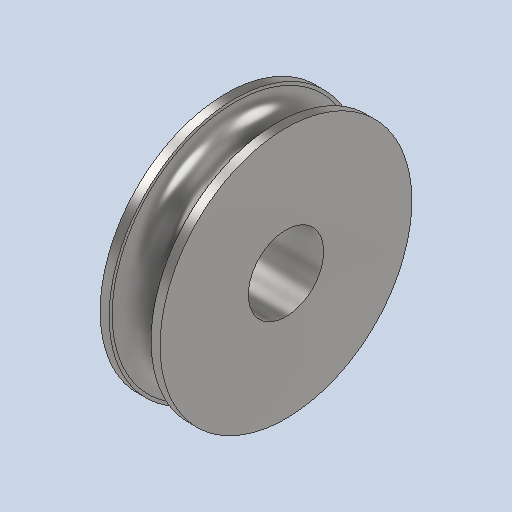
# Autodesk Inventor part: Biegerolle 66
Saved by Autodesk Inventor 2027.1 (Build 311270010, 270A)
## iProperties
Created: 2026-07-29
Part Number: Biegerolle 66
Material: Stahl, Legierung
Document SubType Name: Modeling
Designer: moest
Density: 7.73 g/cm^3
Appearance: Halbpoliert
Author: moest
Autodesk Inventor part; units mm, degrees
ref_plane "YZ Plane" through (0, 0, 0) normal (1, 0, 0) x (0, 1, 0)
ref_plane "XZ Plane" through (0, 0, 0) normal (0, 1, 0) x (-1, 0, 0)
ref_plane "XY Plane" through (0, 0, 0) normal (0, 0, 1) x (1, 0, 0)
sketch "Skizze1" plane through (0, 0, 0) normal (0, 1, 0) x (-1, 0, 0)
  line L0 (0, 0) -> (20, 0)
  line L1 (0, 0) -> (20, 0) construction
  line L2 (20, 0) -> (20, -42)
  line L3 (20, -42) -> (17, -42)
  line L4 (17, -42) -> (17, 0)
  line L5 (0, 0) -> (0, -42)
  line L6 (0, -42) -> (3, -42)
  line L7 (3, -42) -> (3, 0)
  line L8 (3, -42) -> (17, -42)
  line L9 (10, 0) -> (10, -33)
  line L10 (10, -33) -> (3, -33)
  line L11 (10, -33) -> (17, -33)
  line L12 (10, -33) -> (10, -41)
  circle A0 centre (10, -41) radius 7
  line L13 (17, -42) -> (16.9282, -42)
  point P0 (17, -41)
  point P1 (3, -41)
  dimension "d0" = 20
  dimension "d1" = 0
  dimension "d2" = 42
  dimension "d3" = 3
  dimension "d5" = 3
  dimension "d6" = 33
  dimension "d8" = 8
  constraints: 28 end point, 7 point on line, 6 perpendicular, 3 vertical, 2 collinear, 2 horizontal, 1 coincident, 1 midpoint, 3 other
  measures "d0" distance of L0.start L0.end
  measures "d1" distance between parallel lines of L0 L1
  measures "d2" distance of L0.end L2.end
  measures "d3" distance of L2.end L3.end
  measures "d5" distance of L5.end L6.end
  measures "d6" distance of L9.start L9.end
  measures "d8" distance of L9.end L12.end
revolve "Umdrehung1" add sketch "Skizze1" angle 360 about axis through (0, 0, 0) along (-1, 0, 0) contours L0 L7 L6 L5 | L0 L9 L10 L7 | L0 L4 L11 L9 | L10 L12 A0 L7 | L0 L2 L3 L4 | L11 L4 A0 L12
sketch "Skizze2" plane through (-20, 0, 0) normal (-1, 0, 0) x (0, 0, 1)
  circle A0 centre (0, 0) radius 12.55
  dimension "d10" = 25.1
  constraints: 1 centre point, 1 coincident
  measures "d10" diameter of A0
extrude "Extrusion1" cut sketch "Skizze2" against normal blind 90
